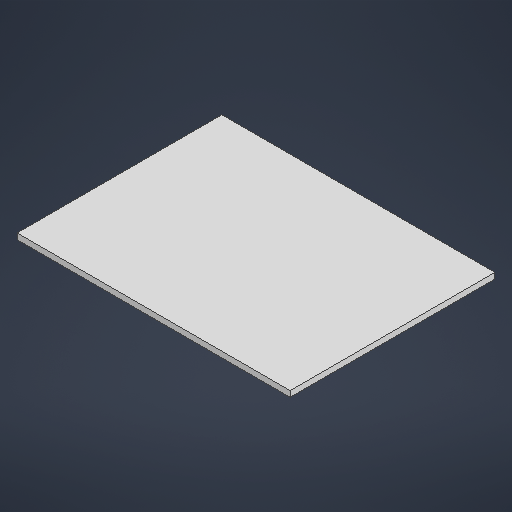
# Autodesk Inventor part: base-1
Saved by Autodesk Inventor 2026.1 (Build 301233000, 233)
## iProperties
Created: 2025-11-11
Part Number: base-1
Material: Generic
Document SubType Name: Modeling
Designer: shiva
Density: 1 g/cm^3
Appearance: Default
Author: shiva
Autodesk Inventor part; units mm, degrees
ref_plane "YZ Plane" through (0, 0, 0) normal (1, 0, 0) x (0, 1, 0)
ref_plane "XZ Plane" through (0, 0, 0) normal (0, 1, 0) x (-1, 0, 0)
ref_plane "XY Plane" through (0, 0, 0) normal (0, 0, 1) x (1, 0, 0)
sketch "Sketch1" plane through (0, 0, 0) normal (0, 0, 1) x (1, 0, 0)
  line L0 (-600, -12.7) -> (600, -12.7)
  line L1 (600, -12.7) -> (600, 12.7)
  line L2 (600, 12.7) -> (-600, 12.7)
  line L3 (-600, 12.7) -> (-600, -12.7)
  line L4 (-600, -12.7) -> (600, 12.7) construction
  line L5 (600, -12.7) -> (-600, 12.7) construction
  point P0 (0, 0)
  dimension "d0" = 1200
  dimension "d1" = 25.4
  constraints: 12 end point, 2 midpoint, 2 parallel, 1 horizontal, 1 perpendicular
  measures "d0" distance of L2.end L1.end
  measures "d1" distance of L1.end L0.end
extrude "Extrusion1" add sketch "Sketch1" along normal blind 900
body "Solid1"
